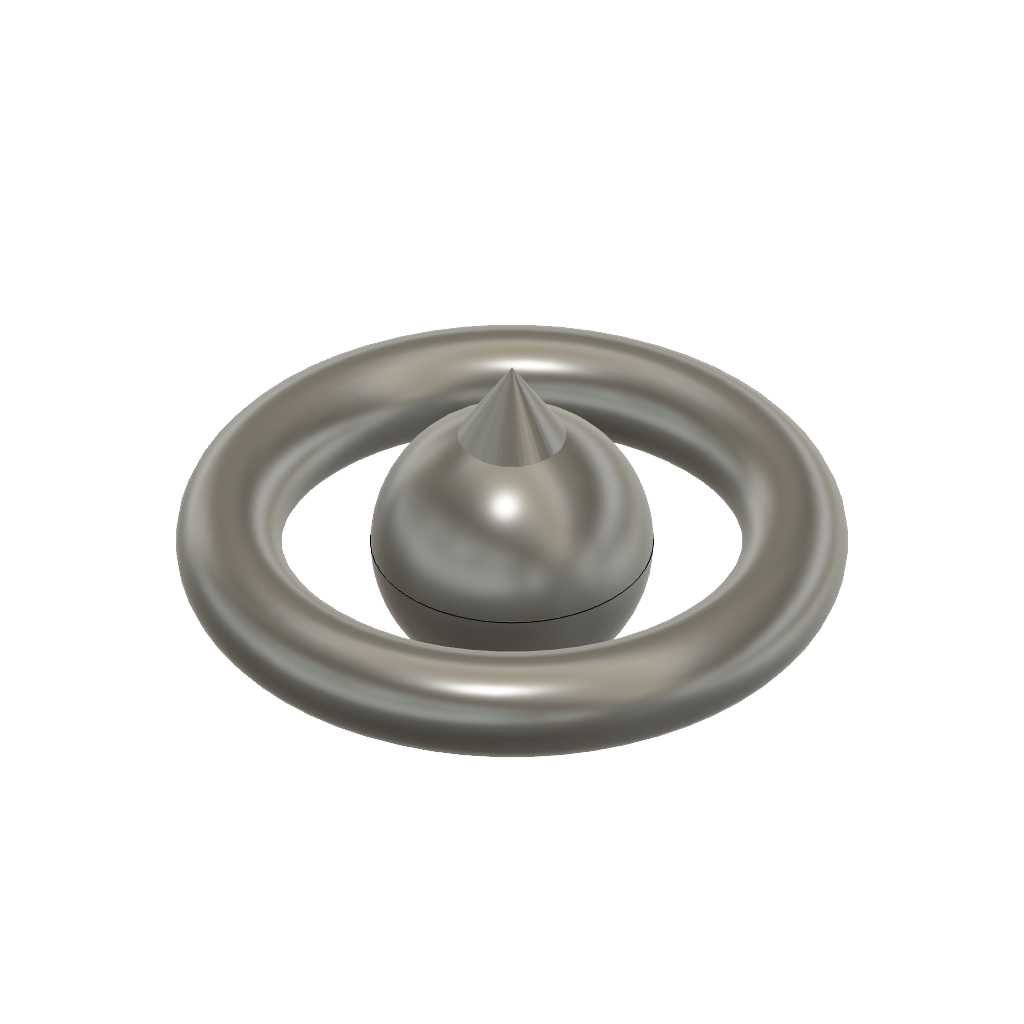
analytic (Autodesk Fusion 360 design; units mm, degrees)
part number: 2026-10-20-19-56-06-257
Autodesk Fusion 360 part; units mm, degrees
sketch "SphereProfile" plane through (0, 0, 0) normal (0, 0, 1) x (1, 0, 0)
  arc A0 (0, 20) -> (0, -20) centre (0, 0) ccw
  line L0 (0, -20) -> (0, 20)
revolve "SphereRevolve" add sketch "SphereProfile" angle 360 about axis through (0, 1.75, 0) along (0, 1, 0) makes body 1
sketch "TorusProfile" plane through (0, 0, 0) normal (0, 0, 1) x (1, 0, 0)
  circle A0 centre (40, 0) radius 7.5
revolve "TorusRevolve" add sketch "TorusProfile" angle 360 about axis through (0, 1.75, 0) along (0, 1, 0) separate body makes body 2
sketch "ConeProfile" plane through (0, 0, 0) normal (0, 0, 1) x (1, 0, 0)
  line L0 (0, 0) -> (20, 0)
  line L1 (20, 0) -> (0, 30)
  line L2 (0, 30) -> (0, 0)
revolve "ConeRevolve" add sketch "ConeProfile" angle 360 about axis through (0, 1.75, 0) along (0, 1, 0) separate body makes body 3
named bodies: "Sphere", "Torus", "Cone"
